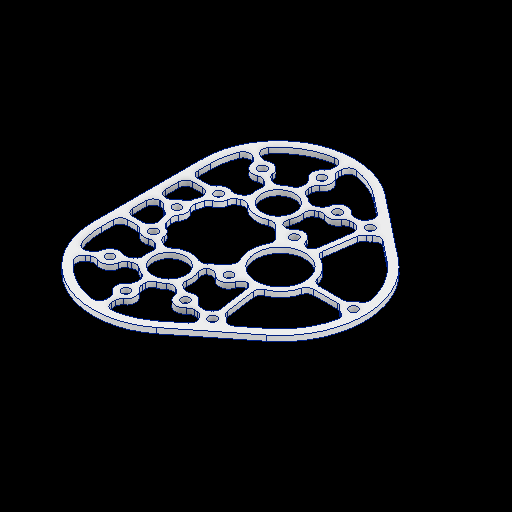
# Autodesk Inventor part: Gearboxes_3_thingy that holds motors and more
Saved by Autodesk Inventor 2027.1 (Build 311270010, 270A)
## iProperties
Created: 2026-06-11
Part Number: Gearboxes_3_thingy that holds motors and more
Material: Aluminum 6061
Document SubType Name: Modeling
Designer: stanr
Density: 2.7 g/cm^3
Appearance: Aluminum - Flat
Mass: 39.0881 g
Surface Area: 157.997 cm^2
Volume: 14.4771 cm^3
Author: stanr
Autodesk Inventor part; units mm, degrees
ref_plane "YZ Plane" through (0, 0, 0) normal (1, 0, 0) x (0, 1, 0)
ref_plane "XZ Plane" through (0, 0, 0) normal (0, 1, 0) x (-1, 0, 0)
ref_plane "XY Plane" through (0, 0, 0) normal (0, 0, 1) x (1, 0, 0)
sketch "Sketch1" plane through (0, 0, 0) normal (0, 1, 0) x (-1, 0, 0)
  circle A0 centre (0, 0) radius 31.75 construction
  circle A1 centre (0, -63.5) radius 31.75 construction
  circle A2 centre (0, 0) radius 9.525
  circle A3 centre (0, -63.5) radius 9.525
  circle A4 centre (0, 0) radius 25.4 construction
  circle A5 centre (0, -63.5) radius 25.4 construction
  circle A6 centre (0, 25.4) radius 2.4892
  circle A7 centre (-21.997, 12.7) radius 2.4892
  circle A8 centre (-21.997, -12.7) radius 2.4892
  circle A9 centre (0, -25.4) radius 2.4892
  circle A10 centre (21.997, -12.7) radius 2.4892
  circle A11 centre (21.997, 12.7) radius 2.4892
  circle A12 centre (0, -88.9) radius 2.4892
  circle A13 centre (21.997, -76.2) radius 2.4892
  circle A14 centre (21.997, -50.8) radius 2.4892
  circle A15 centre (0, -38.1) radius 2.4892
  circle A16 centre (-21.997, -50.8) radius 2.4892
  circle A17 centre (-21.997, -76.2) radius 2.4892
  circle A18 centre (-32.9859, -31.75) radius 36.2585 construction
  circle A19 centre (-32.9859, -31.75) radius 14.2875
  circle A20 centre (0, -63.5) radius 44.45
  circle A21 centre (0, 0) radius 44.45
  circle A22 centre (-32.9859, -31.75) radius 48.9585
  circle A23 centre (-39.4239, 14.2199) radius 2.4892
  circle A24 centre (-39.4239, 14.2199) radius 6.35 construction
  line L0 (-29.8666, 10.7726) -> (-33.4506, 12.0653) construction
  line L1 (-38.5432, 7.9312) -> (-38.0147, 4.1581) construction
  circle A25 centre (-39.4239, -77.7199) radius 2.4892
  circle A26 centre (-39.4239, -77.7199) radius 6.35 construction
  line L2 (-33.4506, -75.5653) -> (-29.8666, -74.2726) construction
  line L3 (-38.5432, -71.4312) -> (-38.0147, -67.6581) construction
  circle A27 centre (27.3566, -31.75) radius 2.4892
  circle A28 centre (27.3566, -31.75) radius 6.35 construction
  line L4 (23.2117, -26.9394) -> (20.7247, -24.053) construction
  line L5 (23.2117, -36.5606) -> (20.7247, -39.447) construction
  line L6 (44.45, 0) -> (44.45, -63.5)
  line L7 (-27.5218, 34.9049) -> (-63.2991, 6.6953)
  line L8 (-63.2991, -70.1953) -> (-27.5218, -98.4049)
  circle A29 centre (-75.5944, -31.75) radius 6.35 construction
  circle A30 centre (-75.5944, -31.75) radius 2.4892
  point P0 (31.1085, -31.75)
  dimension "d4" = 50.8
  dimension "d0" = 63.5
  dimension "d2" = 19.05
  dimension "d5" = 4.9784
  dimension "d8" = 360
  dimension "d12" = 360
  dimension "d14" = 72.517
  dimension "d15" = 28.575
  dimension "d38" = 45.7835
  dimension "d39" = 12.7
  dimension "d40" = 12.7
  dimension "d41" = 12.7
  dimension "d42" = 4.9784
  dimension "d43" = 12.7
  dimension "d44" = 3.81
  constraints: 29 centre point, 18 end point, 18 point on circle, 12 point on line, 10 coincident, 10 tangent, 9 equal radius, 5 equal length, 5 vertical alignment, 1 horizontal alignment, 30 other
  measures "d0" diameter of A0
  measures "d2" diameter of A2
  measures "d5" diameter of A6
  measures "d14" diameter of A18
  measures "d15" diameter of A19
  measures "d38" distance of point (0, 0) A18.centre
  measures "d39" radial gap between concentric circles of A1 A20
  measures "d40" radial gap between concentric circles of A0 A21
  measures "d41" radial gap between concentric circles of A18 A22
  measures "d42" diameter of A23
  measures "d43" diameter of A24
  measures "d44" distance of L0.start L0.end
extrude "Extrusion2" add sketch "Sketch1" along normal blind 3.175 contours A2 A22 A21 A20 | A2 A22 A20 A19 A21 | A22 L7 A21 | A21 A19 A20 A22 | A22 A21 A19 A20 | A20 A21 A22 | A21 L6 A20 | A20 A22 A3 A21 | A19 A21 A22 A3 A20 | A22 A20 L8
sketch "Sketch3" plane through (0, 3.175, 0) normal (0, 1, 0) x (1, 0, 0)
  line L0 (63.2991, 70.1953) -> (27.5218, 98.4049) construction
  arc A0 (27.5218, 98.4049) -> (-44.45, 63.5) centre (0, 63.5) ccw construction
  line L1 (-44.45, 63.5) -> (-44.45, 0) construction
  arc A1 (-44.45, 0) -> (27.5218, -34.9049) centre (0, 0) ccw construction
  line L2 (27.5218, -34.9049) -> (63.2991, -6.6953) construction
  arc A2 (63.2991, -6.6953) -> (63.2991, 70.1953) centre (32.9859, 31.75) ccw construction
  circle A3 centre (0, 63.5) radius 9.525 projected
  circle A4 centre (-27.3566, 31.75) radius 2.4892 projected
  circle A5 centre (39.4239, 77.7199) radius 2.4892 projected
  circle A6 centre (21.997, 76.2) radius 2.4892 projected
  circle A7 centre (21.997, 50.8) radius 2.4892 projected
  circle A8 centre (0, 0) radius 9.525 projected
  circle A9 centre (0, 38.1) radius 2.4892 construction
  circle A10 centre (0, 25.4) radius 2.4892 construction
  circle A11 centre (32.9859, 31.75) radius 14.2875 projected
  circle A12 centre (75.5944, 31.75) radius 2.4892 projected
  circle A13 centre (-21.997, 50.8) radius 2.4892 projected
  circle A14 centre (-21.997, 76.2) radius 2.4892 projected
  circle A15 centre (0, 88.9) radius 2.4892 projected
  circle A16 centre (0, -25.4) radius 2.4892 projected
  circle A17 centre (-21.997, 12.7) radius 2.4892 projected
  circle A18 centre (-21.997, -12.7) radius 2.4892 projected
  circle A19 centre (21.997, -12.7) radius 2.4892 projected
  circle A20 centre (21.997, 12.7) radius 2.4892 projected
  circle A21 centre (39.4239, -14.2199) radius 2.4892 projected
  circle A22 centre (32.9859, 31.75) radius 17.4625
  circle A23 centre (39.4239, 77.7199) radius 5.6642
  circle A24 centre (39.4239, -14.2199) radius 5.6642
  circle A25 centre (75.5944, 31.75) radius 5.6642
  circle A26 centre (21.997, 76.2) radius 5.6642
  circle A27 centre (21.997, -12.7) radius 5.6642
  circle A28 centre (0, -25.4) radius 5.6642
  circle A29 centre (-21.997, -12.7) radius 5.6642
  circle A30 centre (-21.997, 12.7) radius 5.6642
  circle A31 centre (-27.3566, 31.75) radius 5.6642
  circle A32 centre (-21.997, 50.8) radius 5.6642
  circle A33 centre (-21.997, 76.2) radius 5.6642
  circle A34 centre (0, 88.9) radius 5.6642
  circle A35 centre (0, 0) radius 12.7
  circle A36 centre (0, 63.5) radius 12.7
  line L3 (60.3504, 66.4555) -> (24.573, 94.6651)
  arc A37 (24.573, 94.6651) -> (-39.6875, 63.5) centre (0, 63.5) ccw
  line L4 (-39.6875, 63.5) -> (-39.6875, 0)
  arc A38 (-39.6875, 0) -> (24.573, -31.1651) centre (0, 0) ccw
  line L5 (24.573, -31.1651) -> (60.3504, -2.9555)
  arc A39 (60.3504, -2.9555) -> (60.3504, 66.4555) centre (32.9859, 31.75) ccw
  line L6 (21.997, 76.2) -> (-21.997, 50.8)
  line L7 (32.9859, 31.75) -> (39.4239, 77.7199)
  line L8 (32.9859, 31.75) -> (75.5944, 31.75)
  line L9 (32.9859, 31.75) -> (39.4239, -14.2199)
  line L10 (0, 0) -> (-21.997, 12.7)
  line L11 (0, 0) -> (21.997, -12.7)
  line L12 (32.9859, 31.75) -> (0, 0)
  line L13 (32.9859, 31.75) -> (0, 63.5)
  line L14 (-21.997, 50.8) -> (-27.3566, 31.75)
  line L15 (-27.3566, 31.75) -> (-21.997, 12.7)
  line L16 (-27.3566, 31.75) -> (-39.6875, 31.75)
  line L17 (0, 0) -> (0, -39.6875)
  line L18 (21.1304, 73.8665) -> (-20.6438, 49.7482)
  line L19 (-20.6438, 49.7482) -> (-24.3559, 36.554)
  line L20 (19.5429, 76.6162) -> (-23.3503, 51.8518)
  line L21 (-23.3503, 51.8518) -> (-27.4123, 37.4139)
  line L22 (-32.7938, 33.3375) -> (-39.6875, 33.3375)
  line L23 (-32.7938, 30.1625) -> (-39.6875, 30.1625)
  line L24 (-11.706, -4.9254) -> (-18.0821, -8.6066)
  line L25 (-10.1185, -7.675) -> (-16.4946, -11.3562)
  line L26 (-1.5875, -12.6004) -> (-1.5875, -39.6557)
  line L27 (1.5875, -12.6004) -> (1.5875, -39.6557)
  line L28 (19.3558, 20.834) -> (7.9774, 9.8819)
  line L29 (21.5576, 18.5465) -> (10.1792, 7.5944)
  line L30 (33.8256, 14.3077) -> (37.0976, -9.0554)
  line L31 (-24.3559, 26.946) -> (-20.6438, 13.7518)
  line L32 (-20.6438, 13.7518) -> (11.706, -4.9254)
  line L33 (-27.4123, 26.0861) -> (-23.3503, 11.6482)
  line L34 (-23.3503, 11.6482) -> (-11.706, 4.9254)
  line L35 (-10.1185, 7.675) -> (18.0821, -8.6066)
  line L36 (10.1185, -7.675) -> (16.4946, -11.3562)
  line L37 (36.97, 14.7481) -> (40.2419, -8.6151)
  line L38 (50.376, 30.1625) -> (70.1572, 30.1625)
  line L39 (50.376, 33.3375) -> (70.1572, 33.3375)
  line L40 (33.8256, 49.1923) -> (37.0976, 72.5554)
  line L41 (36.97, 48.7519) -> (40.2419, 72.1151)
  line L42 (-10.1185, 71.175) -> (-16.4946, 74.8562)
  line L43 (-11.706, 68.4254) -> (-18.0821, 72.1066)
  line L44 (0, 63.5) -> (0, 103.1875)
  line L45 (1.5875, 76.1004) -> (1.5875, 103.1557)
  line L46 (-1.5875, 76.1004) -> (-1.5875, 103.1557)
  line L47 (19.3558, 42.666) -> (7.9774, 53.6181)
  line L48 (21.5576, 44.9535) -> (10.1792, 55.9056)
  arc A40 (19.1568, 47.2644) -> (23.9911, 46.7177) centre (21.9307, 50.1463) ccw
  arc A41 (17.6857, 40.167) -> (16.955, 44.9769) centre (14.181, 42.095) ccw
  arc A42 (10.2376, 51.4426) -> (5.676, 52.1389) centre (7.4637, 48.5607) ccw
  arc A43 (11.5694, 58.2618) -> (12.4394, 53.7301) centre (15.2133, 56.612) ccw
  arc A44 (14.4229, 69.9939) -> (12.4892, 65.8041) centre (16.4229, 66.5298) ccw
  arc A45 (8.2401, 73.1639) -> (12.8354, 72.7436) centre (10.8354, 76.2077) ccw
  arc A46 (14.3745, 73.6322) -> (16.3573, 76.7253) centre (12.3745, 77.0963) ccw
  arc A47 (19.6321, 71.0531) -> (15.962, 70.8826) centre (17.962, 67.4185) ccw
  arc A48 (30.8221, 49.0779) -> (34.2878, 52.4923) centre (30.3265, 53.0471) ccw
  arc A49 (37.4321, 52.052) -> (39.8265, 47.8169) centre (41.3935, 51.4972) ccw
  arc A50 (42.0261, 72.6888) -> (39.9024, 69.6907) centre (43.8637, 69.1359) ccw
  arc A51 (36.7581, 70.131) -> (35.5397, 73.5972) centre (32.7968, 70.6858) ccw
  arc A52 (1.5875, 79.2375) -> (4.2492, 75.4681) centre (5.5875, 79.2375) ccw
  arc A53 (-4.2492, 75.4681) -> (-1.5875, 79.2375) centre (-5.5875, 79.2375) ccw
  arc A54 (-1.5875, 81.0148) -> (-3.2748, 84.2785) centre (-5.5875, 81.0148) ccw
  arc A55 (3.2748, 84.2785) -> (1.5875, 81.0148) centre (5.5875, 81.0148) ccw
  arc A56 (1.5875, 96.7852) -> (3.2748, 93.5215) centre (5.5875, 96.7852) ccw
  arc A57 (-3.2748, 93.5215) -> (-1.5875, 96.7852) centre (-5.5875, 96.7852) ccw
  arc A58 (-19.6321, 55.9469) -> (-15.962, 56.1174) centre (-17.962, 59.5815) ccw
  arc A59 (-14.4229, 57.0061) -> (-12.4892, 61.1959) centre (-16.4229, 60.4702) ccw
  arc A60 (-14.3745, 53.3678) -> (-16.3573, 50.2747) centre (-12.3745, 49.9037) ccw
  arc A61 (-8.2401, 53.8361) -> (-12.8354, 54.2564) centre (-10.8354, 50.7923) ccw
  arc A62 (-12.4892, 65.8041) -> (-14.4229, 69.9939) centre (-16.4229, 66.5298) ccw
  arc A63 (-15.962, 70.8826) -> (-19.6321, 71.0531) centre (-17.962, 67.4185) ccw
  arc A64 (-12.8354, 72.7436) -> (-8.2401, 73.1639) centre (-10.8354, 76.2077) ccw
  arc A65 (-16.3573, 76.7253) -> (-14.3745, 73.6322) centre (-12.3745, 77.0963) ccw
  arc A66 (49.8462, 36.2961) -> (53.7083, 33.3375) centre (53.7083, 37.3375) ccw
  arc A67 (67.7091, 33.3375) -> (70.9728, 35.0248) centre (67.7091, 37.3375) ccw
  arc A68 (-29.2574, 37.0857) -> (-26.7493, 39.7705) centre (-30.5998, 40.8538) ccw
  arc A69 (-35.2419, 33.3375) -> (-31.9782, 35.0248) centre (-35.2419, 37.3375) ccw
  arc A70 (-39.6875, 37.3375) -> (-35.6875, 33.3375) centre (-35.6875, 37.3375) ccw
  arc A71 (-25.6608, 43.6394) -> (-26.4011, 47.2381) centre (-29.5113, 44.7227) ccw
  arc A72 (-23.6929, 38.9106) -> (-22.9525, 35.3119) centre (-19.8424, 37.8273) ccw
  arc A73 (-20.0962, 45.4643) -> (-22.6044, 42.7795) centre (-18.7539, 41.6962) ccw
  arc A74 (23.9911, 16.7823) -> (19.1568, 16.2356) centre (21.9307, 13.3537) ccw
  arc A75 (16.955, 18.5231) -> (17.6857, 23.333) centre (14.181, 21.405) ccw
  arc A76 (5.676, 11.3611) -> (10.2376, 12.0574) centre (7.4637, 14.9393) ccw
  arc A77 (12.4394, 9.7699) -> (11.5694, 5.2382) centre (15.2133, 6.888) ccw
  arc A78 (12.4892, -2.3041) -> (14.4229, -6.4939) centre (16.4229, -3.0298) ccw
  arc A79 (12.8354, -9.2436) -> (8.2401, -9.6639) centre (10.8354, -12.7077) ccw
  arc A80 (16.3573, -13.2253) -> (14.3745, -10.1322) centre (12.3745, -13.5963) ccw
  arc A81 (15.962, -7.3826) -> (19.6321, -7.5531) centre (17.962, -3.9185) ccw
  arc A82 (34.2878, 11.0077) -> (30.8221, 14.4221) centre (30.3265, 10.4529) ccw
  arc A83 (39.8265, 15.6831) -> (37.4321, 11.448) centre (41.3935, 12.0028) ccw
  arc A84 (39.9024, -6.1907) -> (42.0261, -9.1888) centre (43.8637, -5.6359) ccw
  arc A85 (35.5397, -10.0972) -> (36.7581, -6.631) centre (32.7968, -7.1858) ccw
  arc A86 (4.2492, -11.9681) -> (1.5875, -15.7375) centre (5.5875, -15.7375) ccw
  arc A87 (-1.5875, -15.7375) -> (-4.2492, -11.9681) centre (-5.5875, -15.7375) ccw
  arc A88 (-3.2748, -20.7785) -> (-1.5875, -17.5148) centre (-5.5875, -17.5148) ccw
  arc A89 (1.5875, -17.5148) -> (3.2748, -20.7785) centre (5.5875, -17.5148) ccw
  arc A90 (3.2748, -30.0215) -> (1.5875, -33.2852) centre (5.5875, -33.2852) ccw
  arc A91 (-1.5875, -33.2852) -> (-3.2748, -30.0215) centre (-5.5875, -33.2852) ccw
  arc A92 (-15.962, 7.3826) -> (-19.6321, 7.5531) centre (-17.962, 3.9185) ccw
  arc A93 (-12.4892, 2.3041) -> (-14.4229, 6.4939) centre (-16.4229, 3.0298) ccw
  arc A94 (-12.8354, 9.2436) -> (-8.2401, 9.6639) centre (-10.8354, 12.7077) ccw
  arc A95 (-16.3573, 13.2253) -> (-14.3745, 10.1322) centre (-12.3745, 13.5963) ccw
  arc A96 (-19.6321, -7.5531) -> (-15.962, -7.3826) centre (-17.962, -3.9185) ccw
  arc A97 (-14.3745, -10.1322) -> (-16.3573, -13.2253) centre (-12.3745, -13.5963) ccw
  arc A98 (-8.2401, -9.6639) -> (-12.8354, -9.2436) centre (-10.8354, -12.7077) ccw
  arc A99 (53.7083, 30.1625) -> (49.8462, 27.2039) centre (53.7083, 26.1625) ccw
  arc A100 (70.9728, 28.4752) -> (67.7091, 30.1625) centre (67.7091, 26.1625) ccw
  arc A101 (-26.7493, 23.7295) -> (-29.2574, 26.4143) centre (-30.5998, 22.6462) ccw
  arc A102 (-31.9782, 28.4752) -> (-35.2419, 30.1625) centre (-35.2419, 26.1625) ccw
  arc A103 (-35.6875, 30.1625) -> (-39.6875, 26.1625) centre (-35.6875, 26.1625) ccw
  arc A104 (-26.4011, 16.2619) -> (-25.6608, 19.8606) centre (-29.5113, 18.7773) ccw
  arc A105 (-22.6044, 20.7205) -> (-20.0962, 18.0357) centre (-18.7539, 21.8038) ccw
  arc A106 (-22.9525, 28.1881) -> (-23.6929, 24.5894) centre (-19.8424, 25.6727) ccw
  arc A107 (6.2138, 102.698) -> (1.5875, 98.7474) centre (5.5875, 98.7474) ccw
  arc A108 (-1.5875, 98.7474) -> (-6.2138, 102.698) centre (-5.5875, 98.7474) ccw
  arc A109 (1.5875, -35.2474) -> (6.2138, -39.198) centre (5.5875, -35.2474) ccw
  arc A110 (-6.2138, -39.198) -> (-1.5875, -35.2474) centre (-5.5875, -35.2474) ccw
  arc A111 (49.5579, 74.9651) -> (43.9119, 74.2643) centre (47.0813, 71.824) ccw
  arc A112 (35.0167, 81.278) -> (34.3811, 86.9317) centre (31.9044, 83.7906) ccw
  arc A113 (73.5781, 37.0432) -> (76.0519, 41.6799) centre (72.1542, 40.7812) ccw
  arc A114 (43.9119, -10.7643) -> (49.5579, -11.4651) centre (47.0813, -8.324) ccw
  arc A115 (34.3811, -23.4317) -> (35.0167, -17.778) centre (31.9044, -20.2906) ccw
  arc A116 (76.0519, 21.8201) -> (73.5781, 26.4568) centre (72.1542, 22.7188) ccw
  line L49 (0, 63.5) -> (-34.3704, 83.3437)
  line L50 (0, 0) -> (-34.3704, -19.8437)
  arc A117 (-14.4229, -6.4939) -> (-12.4892, -2.3041) centre (-16.4229, -3.0298) ccw
  line L51 (-27.4995, -14.0438) -> (-35.1366, -18.4531)
  line L52 (-25.912, -16.7934) -> (-33.5491, -21.2027)
  line L53 (-27.4995, 77.5438) -> (-35.1366, 81.9531)
  line L54 (-25.912, 80.2934) -> (-33.5491, 84.7027)
  arc A118 (-27.6368, 75.6747) -> (-29.6196, 78.7678) centre (-31.6196, 75.3037) ccw
  arc A119 (-28.0321, 81.5174) -> (-24.362, 81.3469) centre (-26.0321, 84.9815) ccw
  arc A120 (-30.8396, 88.4803) -> (-29.7314, 82.4985) centre (-27.7314, 85.9626) ccw
  arc A121 (-31.3189, 79.7489) -> (-37.0534, 77.7177) centre (-33.3189, 76.2848) ccw
  arc A122 (-29.6196, -15.2678) -> (-27.6368, -12.1747) centre (-31.6196, -11.8037) ccw
  arc A123 (-24.362, -17.8469) -> (-28.0321, -18.0174) centre (-26.0321, -21.4815) ccw
  arc A124 (-29.7314, -18.9985) -> (-30.8396, -24.9803) centre (-27.7314, -22.4626) ccw
  arc A125 (-37.0534, -14.2177) -> (-31.3189, -16.2489) centre (-33.3189, -12.7848) ccw
  line L55 (21.997, -12.7) -> (39.4239, -14.2199)
  line L56 (33.8693, -15.329) -> (27.2757, -14.7539)
  line L57 (34.1452, -12.166) -> (27.5516, -11.5909)
  arc A126 (31.7064, -11.9533) -> (35.1044, -10.5559) centre (32.054, -7.9684) ccw
  arc A127 (26.8856, -9.8391) -> (29.9904, -11.8036) centre (30.3379, -7.8187) ccw
  arc A128 (34.5353, -17.0808) -> (31.4306, -15.1163) centre (31.083, -19.1011) ccw
  arc A129 (29.7145, -14.9666) -> (26.3166, -16.364) centre (29.367, -18.9515) ccw
  line L58 (21.997, 76.2) -> (39.4239, 77.7199)
  line L59 (33.8693, 78.829) -> (27.2757, 78.2539)
  line L60 (34.1452, 75.666) -> (27.5516, 75.0909)
  arc A130 (35.1044, 74.0559) -> (31.7064, 75.4533) centre (32.054, 71.4684) ccw
  arc A131 (29.9904, 75.3036) -> (26.8856, 73.3391) centre (30.3379, 71.3187) ccw
  arc A132 (31.4306, 78.6163) -> (34.5353, 80.5808) centre (31.083, 82.6011) ccw
  arc A133 (26.3166, 79.864) -> (29.7145, 78.4666) centre (29.367, 82.4515) ccw
  line L61 (-21.997, 50.8) -> (-39.6875, 50.8)
  line L62 (-21.997, 50.8) -> (-4.3066, 50.8) construction
  line L63 (-27.4342, 52.3875) -> (-39.6875, 52.3875)
  line L64 (-27.4342, 49.2125) -> (-39.6875, 49.2125)
  arc A134 (-26.6186, 47.5252) -> (-29.8823, 49.2125) centre (-29.8823, 45.2125) ccw
  arc A135 (-35.6875, 49.2125) -> (-39.6875, 45.2125) centre (-35.6875, 45.2125) ccw
  arc A136 (-29.8823, 52.3875) -> (-26.6186, 54.0748) centre (-29.8823, 56.3875) ccw
  arc A137 (-39.6875, 56.3875) -> (-35.6875, 52.3875) centre (-35.6875, 56.3875) ccw
  line L65 (-21.997, 12.7) -> (-39.6875, 12.7)
  line L66 (-27.4342, 11.1125) -> (-39.6875, 11.1125)
  line L67 (-27.4342, 14.2875) -> (-39.6875, 14.2875)
  arc A138 (-29.8823, 14.2875) -> (-26.6186, 15.9748) centre (-29.8823, 18.2875) ccw
  arc A139 (-39.6875, 18.2875) -> (-35.6875, 14.2875) centre (-35.6875, 18.2875) ccw
  arc A140 (-26.6186, 9.4252) -> (-29.8823, 11.1125) centre (-29.8823, 7.1125) ccw
  arc A141 (-35.6875, 11.1125) -> (-39.6875, 7.1125) centre (-35.6875, 7.1125) ccw
  circle A142 centre (21.997, 50.8) radius 5.6642
  arc A143 (27.491, 52.1783) -> (31.6718, 49.163) centre (31.3708, 53.1516) ccw
  arc A144 (11.9117, 54.238) -> (17.7118, 54.5041) centre (14.6857, 57.1199) ccw
  circle A145 centre (21.997, 12.7) radius 5.6642
  arc A146 (17.7118, 8.9959) -> (11.9117, 9.262) centre (14.6857, 6.3801) ccw
  arc A147 (31.6718, 14.337) -> (27.491, 11.3217) centre (31.3708, 10.3484) ccw
  point P0 (67.7091, 30.1625)
  point P1 (53.7083, 30.1625)
  point P2 (39.8265, 15.6831)
  point P3 (42.0261, -9.1888)
  point P4 (45.029, -15.036)
  point P5 (76.8349, 26.2233)
  point P6 (38.91, 83.3607)
  point P7 (76.8349, 37.2767)
  point P8 (45.029, 78.536)
  point P9 (1.5875, -35.2474)
  point P10 (38.91, -19.8607)
  point P11 (35.5397, -10.0972)
  point P12 (36.7581, -6.631)
  point P13 (30.8221, 14.4221)
  point P14 (23.9911, 16.7823)
  point P15 (19.1568, 16.2356)
  point P16 (12.4394, 9.7699)
  point P17 (11.5694, 5.2382)
  point P18 (12.4892, -2.3041)
  point P19 (14.4229, -6.4939)
  point P20 (15.962, -7.3826)
  point P21 (16.3573, -13.2253)
  point P22 (14.3745, -10.1322)
  point P23 (12.8354, -9.2436)
  point P24 (8.2401, -9.6639)
  point P25 (4.2492, -11.9681)
  point P26 (1.5875, -15.7375)
  point P27 (1.5875, -17.5148)
  point P28 (3.2748, -20.7785)
  point P29 (3.2748, -30.0215)
  point P30 (1.5875, -33.2852)
  point P31 (-16.5711, 74.5745)
  point P32 (-15.8786, 74.5006)
  point P33 (-12.8354, 72.7436)
  point P34 (-8.2401, 73.1639)
  point P35 (-3.2748, 93.5215)
  point P36 (16.955, 18.5231)
  point P37 (-12.8354, 54.2564)
  point P38 (-14.3745, 53.3678)
  point P39 (-16.3573, 50.2747)
  point P40 (-22.6044, 42.7795)
  point P41 (-23.6929, 38.9106)
  point P42 (-23.6929, 24.5894)
  point P43 (-22.6044, 20.7205)
  point P44 (-20.0962, 18.0357)
  point P45 (-16.3573, 13.2253)
  point P46 (-14.3745, 10.1322)
  point P47 (-12.8354, 9.2436)
  point P48 (5.676, 11.3611)
  point P49 (10.2376, 12.0574)
  point P50 (-6.2138, -39.198)
  point P51 (-1.5875, -35.2474)
  point P52 (-1.5875, -33.2852)
  point P53 (-3.2748, -30.0215)
  point P54 (-3.2748, -20.7785)
  point P55 (-1.5875, -17.5148)
  point P56 (-1.5875, -15.7375)
  point P57 (-4.2492, -11.9681)
  point P58 (-8.2401, -9.6639)
  point P59 (-12.8354, -9.2436)
  point P60 (-14.3745, -10.1322)
  point P61 (-16.3573, -13.2253)
  point P62 (-19.6321, -7.5531)
  point P63 (-15.962, -7.3826)
  point P64 (-12.4892, 2.3041)
  point P65 (-14.4229, 6.4939)
  point P66 (-15.962, 7.3826)
  point P67 (-19.6321, 7.5531)
  point P68 (-26.7493, 23.7295)
  point P69 (-29.2574, 26.4143)
  point P70 (-35.2419, 30.1625)
  point P71 (-35.6875, 30.1625)
  point P72 (-39.6875, 26.1625)
  point P73 (76.0519, 21.8201)
  point P74 (43.9119, -10.7643)
  point P75 (49.5579, -11.4651)
  point P76 (34.3811, -23.4317)
  point P77 (35.0167, -17.778)
  point P78 (-24.9978, 45.996)
  point P79 (-1.5875, 83.4628)
  point P80 (-11.706, 58.5746)
  point P81 (-18.0821, 54.8934)
  point P82 (-1.5875, 94.3372)
  point P83 (10.1185, 71.175)
  point P84 (-29.7314, -18.9985)
  point P85 (-30.8396, -24.9803)
  point P86 (-24.362, -17.8469)
  point P87 (-28.0321, -18.0174)
  point P88 (-29.6196, -15.2678)
  point P89 (-37.0534, -14.2177)
  point P90 (-31.3189, -16.2489)
  point P91 (26.3166, -16.364)
  point P92 (34.5353, 80.5808)
  point P93 (29.7145, 78.4666)
  point P94 (35.1044, 74.0559)
  point P95 (-26.6186, 9.4252)
  point P96 (-29.8823, 11.1125)
  point P97 (-35.6875, 11.1125)
  point P98 (-26.6186, 15.9748)
  point P99 (-39.6875, 18.2875)
  point P100 (-35.6875, 52.3875)
  point P101 (-29.8823, 52.3875)
  point P102 (27.0068, 48.157)
  point P103 (16.4023, 49.9156)
  point P104 (12.1872, 9.5039)
  point P105 (31.2436, 14.3463)
  point P106 (27.491, 11.3217)
  point P107 (12.1872, 53.9961)
  point P108 (31.2436, 49.1537)
  point P109 (11.706, 68.4254)
  point P110 (-10.1185, 55.825)
  dimension "d64" = 3.175
  dimension "d75" = 3.175
  dimension "d76" = 3.175
  dimension "d77" = 4.7625
  dimension "d78" = 1.5875
  dimension "d79" = 1.5875
  dimension "d80" = 1.5875
  dimension "d81" = 1.5875
  dimension "d86" = 1.5875
  dimension "d87" = 1.5875
  dimension "d90" = 1.5875
  dimension "d91" = 1.5875
  dimension "d92" = 1.5875
  dimension "d103" = 1.5875
  dimension "d104" = 1.5875
  dimension "d105" = 1.5875
  dimension "d106" = 1.5875
  dimension "d107" = 1.5875
  dimension "d108" = 1.5875
  dimension "d109" = 1.5875
  dimension "d110" = 1.5875
  dimension "d111" = 1.5875
  dimension "d114" = 1.5875
  dimension "d115" = 1.5875
  dimension "d116" = 1.5875
  dimension "d117" = 1.5875
  dimension "d118" = 4
  dimension "d119" = 4
  dimension "d120" = 4
  dimension "d121" = 4
  dimension "d122" = 4
  dimension "d123" = 4
  dimension "d124" = 4
  dimension "d125" = 4
  dimension "d126" = 4
  dimension "d127" = 4
  dimension "d128" = 4
  dimension "d129" = 4
  dimension "d130" = 4
  dimension "d131" = 4
  dimension "d132" = 4
  dimension "d133" = 4
  dimension "d135" = 4
  dimension "d136" = 4
  dimension "d137" = 4
  dimension "d138" = 4
  dimension "d139" = 4
  dimension "d140" = 4
  dimension "d142" = 4
  dimension "d143" = 4
  dimension "d145" = 4
  dimension "d146" = 4
  dimension "d147" = 4
  dimension "d148" = 4
  dimension "d149" = 4
  dimension "d152" = 4
  dimension "d153" = 4
  dimension "d154" = 4
  dimension "d156" = 1.5875
  dimension "d157" = 1.5875
  dimension "d158" = 4
  dimension "d159" = 4
  dimension "d160" = 1.5875
  dimension "d161" = 1.5875
  constraints: 261 point on circle, 193 symmetric about line, 128 end point, 119 centre point, 63 tangent, 49 point on line, 25 parallel, 15 coincident, 8 equal radius, 3 horizontal, 2 vertical, 1 collinear, 198 other
  measures "d75" radial gap between concentric circles of A5 A23
  measures "d77" radial gap between concentric circles of A2 A39
  measures "d78" distance between parallel lines of L6 L18
  measures "d79" distance between parallel lines of L6 L20
  measures "d80" distance between parallel lines of L16 L22
  measures "d81" distance between parallel lines of L16 L23
  measures "d86" distance between parallel lines of L17 L26
  measures "d87" distance between parallel lines of L17 L27
  measures "d90" distance between parallel lines of L12 L28
  measures "d91" distance between parallel lines of L12 L29
  measures "d92" distance between parallel lines of L9 L30
  measures "d103" distance between parallel lines of L15 L31
  measures "d104" distance between parallel lines of L15 L33
  measures "d105" distance between parallel lines of L11 L35
  measures "d106" distance between parallel lines of L11 L36
  measures "d107" distance between parallel lines of L9 L37
  measures "d108" distance between parallel lines of L8 L38
  measures "d109" distance between parallel lines of L8 L39
  measures "d110" distance between parallel lines of L7 L40
  measures "d111" distance between parallel lines of L7 L41
  measures "d114" distance between parallel lines of L44 L45
  measures "d115" distance between parallel lines of L44 L46
  measures "d116" distance between parallel lines of L13 L47
  measures "d117" distance between parallel lines of L13 L48
  measures "d118" radius of A40
  measures "d119" radius of A41
  measures "d120" radius of A42
  measures "d121" radius of A43
  measures "d122" radius of A44
  measures "d123" radius of A45
  measures "d124" radius of A46
  measures "d125" radius of A47
  measures "d126" radius of A48
  measures "d127" radius of A49
  measures "d128" radius of A50
  measures "d129" radius of A51
  measures "d130" radius of A52
  measures "d131" radius of A53
  measures "d132" radius of A54
  measures "d133" radius of A55
  measures "d135" radius of A56
  measures "d136" radius of A58
  measures "d137" radius of A59
  measures "d138" radius of A62
  measures "d139" radius of A63
  measures "d140" radius of A66
  measures "d142" radius of A67
  measures "d143" radius of A68
  measures "d145" radius of A70
  measures "d146" radius of A71
  measures "d147" radius of A69
  measures "d148" radius of A107
  measures "d149" radius of A108
  measures "d152" radius of A111
  measures "d153" radius of A112
  measures "d154" radius of A113
  measures "d156" distance between parallel lines of L42 L49
  measures "d157" distance between parallel lines of L49 L43
  measures "d158" radius of A65
  measures "d159" radius of A64
  measures "d160" distance between parallel lines of L50 L24
  measures "d161" distance between parallel lines of L50 L25
extrude "Extrusion4" cut sketch "Sketch3" against normal blind 4 contours A44 L18 A47 A26 A131 L60 A130 A23 A51 L40 A48 A143 A142 A144 A43 A36 | A36 A42 L47 A41 A22 A75 L28 A76 A35 A94 L32 A95 A30 A105 L31 A106 A31 A72 L19 A73 A32 A60 L18 A61 | A36 A52 L45 A55 A34 A56 A107 A37 L3 A112 A23 A132 L59 A133 A26 A46 L20 A45 | A59 L20 A58 A32 A136 L63 A137 L4 A37 A121 L53 A118 A33 A63 L43 A62 A36 | A36 A64 L42 A65 A33 A119 L54 A120 A37 A108 L46 A57 A34 A54 A53 | A49 L41 A50 A23 A111 L3 A39 A113 A25 A67 L39 A66 A22 | A99 L38 A100 A25 A116 A39 L5 A114 A24 A84 L37 A83 A22 | L30 A85 A24 A126 L57 A127 A27 A81 L35 A78 A35 A77 A146 A145 A147 A82 | A71 L21 A68 A31 A69 L22 A70 L4 A135 L64 A134 A32 | A24 A115 L5 A38 A109 L27 A90 A28 A89 A86 A35 A79 L36 A80 A27 A129 L56 A128 | A35 A117 L24 A96 A29 A122 L51 A125 A38 L4 A141 L66 A140 A30 A92 L34 A93 | A35 A87 L26 A88 A28 A91 A110 A38 A124 L52 A123 A29 A97 L25 A98 | A31 A101 L33 A104 A30 A138 L67 A139 L4 A103 L23 A102
body "Solid2"
